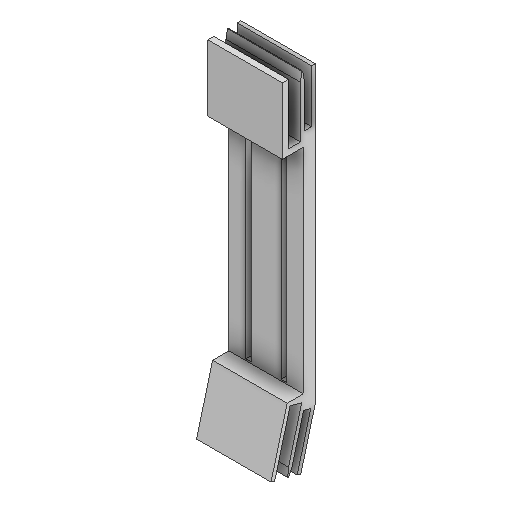
# Autodesk Inventor part: TOP
Saved by Autodesk Inventor 2026 (Build 300175050, 175E)
## iProperties
Created: 2026-11-25
Part Number: TOP
Material: Generic
Document SubType Name: Modeling
Designer: David Zindović
Density: 1 g/cm^3
Appearance: Default
Author: David Zindović
Autodesk Inventor part; units mm, degrees
ref_plane "YZ Plane" through (0, 0, 0) normal (1, 0, 0) x (0, 1, 0)
ref_plane "XZ Plane" through (0, 0, 0) normal (0, 1, 0) x (-1, 0, 0)
sketch "Sketch1" plane through (0, 0, 0) normal (0, 0, 1) x (1, 0, 0)
  line L0 (-24.75, 80) -> (24.75, 80)
  line L1 (24.75, 80) -> (24.75, -80)
  line L2 (24.75, -80) -> (-24.75, -80)
  line L3 (-24.75, -80) -> (-24.75, 80)
  line L4 (-13.5, 70) -> (-10, 70)
  line L5 (-10, 70) -> (-10, -70)
  line L6 (-10, -70) -> (-13.5, -70)
  line L7 (-13.5, -70) -> (-13.5, 70)
  line L8 (10, -70) -> (13.5, -70)
  line L9 (13.5, -70) -> (13.5, 70)
  line L10 (13.5, 70) -> (10, 70)
  line L11 (10, 70) -> (10, -70)
  point P0 (0, 0)
  point P1 (0, 80)
  point P2 (24.75, 0)
  point P3 (10, 0)
  dimension "d0" = 49.5
  dimension "d1" = 160
  dimension "d4" = 10
  dimension "d5" = 10
  dimension "d6" = 3.5
  dimension "d7" = 3.5
  dimension "d8" = 140
  constraints: 24 end point, 6 parallel, 4 horizontal alignment, 3 horizontal, 3 midpoint, 3 perpendicular, 2 point on line, 1 vertical alignment
  measures "d0" distance of L0.start L0.end
  measures "d1" distance of L0.end L1.end
  measures "d4" distance from line of L5 point (0, 0)
  measures "d5" distance from line of point (0, 0) L11
  measures "d6" distance of L4.start L4.end
  measures "d7" distance of L9.end L10.end
  measures "d8" distance of L5.end L4.end
extrude "Extrusion1" add sketch "Sketch1" along normal blind 10
sketch "Sketch2" plane through (-24.75, 80, 0) normal (0, 1, 0) x (1, 0, 0)
  line L0 (49.5, -10) -> (0, -10) projected
  line L1 (49.5, 0) -> (49.5, -10) projected
  line L2 (0, -10) -> (49.5, -10)
  line L3 (49.5, -10) -> (49.5, -7.5)
  line L4 (49.5, -7.5) -> (0, -7.5)
  line L5 (0, -7.5) -> (0, -10)
  line L6 (49.5, 0) -> (0, 0) projected
  line L7 (0, 0) -> (0, -10) projected
  line L8 (49.5, 0) -> (0, 0)
  line L9 (0, 0) -> (0, -2.5)
  line L10 (0, -2.5) -> (49.5, -2.5)
  line L11 (49.5, -2.5) -> (49.5, 0)
  line L12 (49.5, -18) -> (0, -18)
  line L13 (0, -18) -> (0, -22)
  line L14 (0, -22) -> (49.5, -22)
  line L15 (49.5, -22) -> (49.5, -18)
  point P0 (24.75, 0)
  dimension "d9" = 2.5
  dimension "d12" = 2.5
  dimension "d13" = 4
  dimension "d14" = 8
  constraints: 24 end point, 6 parallel, 4 point on line, 3 horizontal, 3 perpendicular
  measures "d9" distance of L3.end L2.end
  measures "d12" distance of L9.end L8.end
  measures "d13" distance of L12.end L13.end
  measures "d14" distance between parallel lines of L12 L0
extrude "Extrusion2" add sketch "Sketch2" along normal blind 35 contours L0 L5 L4 L1 | L10 L7 L6 L1 | L15 L14 L13 L12
sketch "Sketch3" plane through (0, 0, 10) normal (0, 0, 1) x (1, 0, 0)
  line L0 (-24.75, -80) -> (-24.75, 115) projected
  line L1 (24.75, -80) -> (24.75, 115) projected
  line L2 (-24.75, 75) -> (24.75, 75)
  line L3 (24.75, 75) -> (24.75, 63)
  line L4 (24.75, 63) -> (-24.75, 63)
  line L5 (-24.75, 63) -> (-24.75, 75)
  line L6 (-24.75, 80) -> (24.75, 80) projected
  point P0 (0, 0)
  dimension "d15" = 12
  dimension "d16" = 5
  constraints: 8 end point, 2 parallel, 2 point on line, 1 horizontal, 1 perpendicular
  measures "d15" distance of L2.end L3.end
  measures "d16" distance between parallel lines of L6 L2
loft "Loft1" [suppressed]
ref_plane "Work Plane1" through (-24.75, -80, 10) normal (0, -0.9659258, 0.258819) x (1, 0, 0)
sketch "Sketch4" plane through (-24.75, -80, 10) normal (0, -0.9659258, 0.258819) x (1, 0, 0)
  line L0 (0, -9.659258) -> (49.5, -9.659258)
  line L1 (0, -9.659258) -> (0, 40.810456)
  line L2 (49.5, -9.659258) -> (0, -9.659258)
  line L3 (0, -9.659258) -> (0, -7.159258)
  line L4 (0, -7.159258) -> (49.5, -7.159258)
  line L5 (49.5, -7.159258) -> (49.5, -9.659258)
  line L6 (49.5, -9.659258) -> (49.5, 40.810456)
  line L7 (0, -2.159258) -> (49.5, -2.159258)
  line L8 (49.5, -2.159258) -> (49.5, 0.340742)
  line L9 (49.5, 0.340742) -> (0, 0.340742)
  line L10 (0, 0.340742) -> (0, -2.159258)
  line L11 (49.5, 10.840742) -> (0, 10.840742)
  line L12 (0, 10.840742) -> (0, 8.340742)
  line L13 (0, 8.340742) -> (49.5, 8.340742)
  line L14 (49.5, 8.340742) -> (49.5, 10.840742)
  point P0 (24.75, 11.046265)
  point P1 (49.5, 8.340742)
  point P2 (0, 10.840742)
  point P3 (0, 0.340742)
  point P4 (49.5, -2.159258)
  dimension "d22" = 2.5
  dimension "d23" = 2.5
  dimension "d25" = 2.5
  dimension "d26" = 8
  dimension "d27" = 5
  constraints: 24 end point, 6 parallel, 5 point on line, 3 horizontal, 3 perpendicular
  measures "d22" distance of L2.end L3.end
  measures "d23" distance of L8.end L7.end
  measures "d25" distance between parallel lines of L11 L13
  measures "d26" distance between parallel lines of L9 L13
  measures "d27" distance between parallel lines of L7 L4
extrude "Extrusion3" add sketch "Sketch4" along normal blind 35 contours L1 L4 L5 L0 | L1 L9 L6 L7 | L1 L11 L6 L13
sketch "Sketch5" plane through (-24.75, -80, 0) normal (-1, 0, 0) x (0, 0, 1)
  line L0 (3.084688, -1.852952) -> (0.669873, -2.5)
  line L1 (0, 0) -> (0, 195)
  line L2 (0.669873, -2.5) -> (0, 0)
  line L3 (10, 0) -> (10.329131, 0.08819)
  line L4 (3.084688, -1.852952) -> (10.329131, 0.08819)
  line L5 (20.471352, 2.80579) -> (18.056538, 2.158743)
  line L6 (18.056538, 2.158743) -> (16.762443, 6.988372)
  line L7 (20.471352, 2.80579) -> (10, 22.602031)
  line L8 (10, 0) -> (10, 195)
  line L9 (0, 0) -> (10, 0)
  line L10 (0, 0) -> (10, 0)
  line L11 (16.762443, 6.988372) -> (10, 6.628707)
  line L12 (10.329131, 0.08819) -> (10, 2.886751)
  line L13 (10, 0) -> (10, 195)
  point P0 (0, 80)
  point P1 (10, 143)
  point P2 (10, 2.886751)
  dimension "d30" = 5
  constraints: 14 end point, 3 point on line, 2 collinear, 1 perpendicular
  measures "d30" distance of L5.end L6.end
extrude "Extrusion4" [suppressed]
sketch "Sketch6" plane through (24.75, 80, 2.5) normal (1, 0, 0) x (0, 0, -1)
  line L0 (-7.5, -5) -> (-15.5, 0) projected
  line L1 (-15.5, 0) -> (-15.5, -5)
  line L2 (-15.5, -5) -> (-7.5, -5)
  line L3 (-19.5, 0) -> (-19.5, -9)
  line L4 (-19.5, -9) -> (-7.5, -19)
  line L5 (-7.5, -160) -> (-7.5, 35) projected
  line L6 (-7.5, -19) -> (-7.5, -5)
  line L7 (-15.5, 0) -> (-15.5, 35) projected
  line L8 (-15.5, 0) -> (-19.5, 0)
  line L9 (-19.5, -9) -> (-7.5, -9)
  point P0 (2.5, -80)
  point P1 (-7.5, -137.397969)
  point P2 (-7.5, -17)
  point P3 (-7.5, -5)
  point P4 (-7.5, -9)
  dimension "d35" = 4
  dimension "d36" = 10
  constraints: 14 end point, 2 perpendicular, 2 point on line, 2 vertical, 1 collinear, 1 horizontal
  measures "d35" horizontal distance of L1.end L3.end
  measures "d36" vertical distance of L3.end L4.end
extrude "Extrusion5" cut sketch "Sketch6" against normal up to surface (49.5 mm away) contours L2 L1 L0
extrude "Extrusion6" add sketch "Sketch6" against normal up to surface (49.5 mm away) contours L5 L9 L3 L8 L1 L2
chamfer "Chamfer1" distance 1 angle 80 2 edges at (0, 115, 10) (0, 115, 7.5) measured on face at (0, 115, 8) measured on face at (0, 115, 9.5)
chamfer "Chamfer2" distance 1 angle 80 2 edges at (0, -113.7192, 19.3878) (0, -114.3663, 16.973) measured on face at (0, -114.2369, 17.4559) measured on face at (0, -113.8486, 18.9048)
sketch "Sketch7" plane through (0, 0, 10) normal (0, 0, 1) x (1, 0, 0)
  line L0 (-24.75, -80) -> (-24.75, 71)
  line L1 (24.75, -80) -> (24.75, 71)
  line L2 (10, -70) -> (10, 70)
  line L3 (13.5, 70) -> (13.5, -70)
  line L4 (-10, 70) -> (-10, -70)
  line L5 (-13.5, -70) -> (-13.5, 70)
  line L6 (13.5, -70) -> (10, -70)
  line L7 (-10, -70) -> (-13.5, -70)
  line L8 (-24.75, -80) -> (24.75, -80)
  line L9 (-24.75, 109.328718) -> (24.75, 109.328718)
  line L10 (-24.75, 75) -> (-24.75, 109.328718)
  line L11 (-24.75, 75) -> (24.75, 75)
  line L12 (24.75, 75) -> (24.75, 109.328718)
  line L13 (24.75, 71) -> (-24.75, 71)
  line L14 (10, 70) -> (13.5, 70)
  line L15 (-13.5, 70) -> (-10, 70)
  point P0 (0, 0)
extrude "Extrusion7" cut sketch "Sketch7" against normal blind 2 contours L0 L13 L1 L8
sketch "Sketch8" plane through (-24.75, -80, 0) normal (-1, 0, 0) x (0, 0, 1)
  line L0 (0.669873, -2.5) -> (9.72854, -36.307404)
  line L1 (0, 0) -> (0, 195)
  line L2 (0.669873, -2.5) -> (0, 0)
  line L3 (7.914317, -0.558857) -> (10.329131, 0.08819)
  line L4 (3.084688, -1.852952) -> (7.914317, -0.558857)
  line L5 (0, 10) -> (8, 10)
  line L6 (20.471352, 2.80579) -> (18.056538, 2.158743)
  line L7 (20.471352, 2.80579) -> (18.81017, 9.005409)
  line L8 (18.81017, 9.005409) -> (8, 9.005409)
  line L9 (8, 0) -> (8, 151)
  line L10 (10.329131, 0.08819) -> (17.919962, -28.241176)
  line L11 (16.891852, 6.505409) -> (8.609643, 6.505409)
  line L12 (10.329131, 0.08819) -> (8.609643, 6.505409)
  line L13 (18.056538, 2.158743) -> (16.891852, 6.505409)
  line L14 (0, 0) -> (8, 0)
  line L15 (0, 0) -> (8, 0)
  line L16 (3.084688, -1.852952) -> (0.669873, -2.5)
  line L17 (0.669873, -2.5) -> (3.084688, -1.852952)
  line L18 (16.891852, 6.505409) -> (9.164446, 4.434857)
  point P0 (0, 80)
  dimension "d49" = 4.5
  dimension "d50" = 2.5
  constraints: 20 end point, 4 collinear, 2 horizontal, 2 perpendicular, 2 point on line, 1 parallel
  measures "d49" distance of L6.end L11.start
  measures "d50" distance between parallel lines of L11 L8
extrude "Extrusion8" add sketch "Sketch8" against normal up to surface (49.5 mm away) contours L14 L9 L8 L7 L6 L13 L11 L12 L3 L4 L16 L2 | L12 L11 L18
equation "\"d5\" = d4"
equation "\"d7\" = d6"
body "Solid1"
